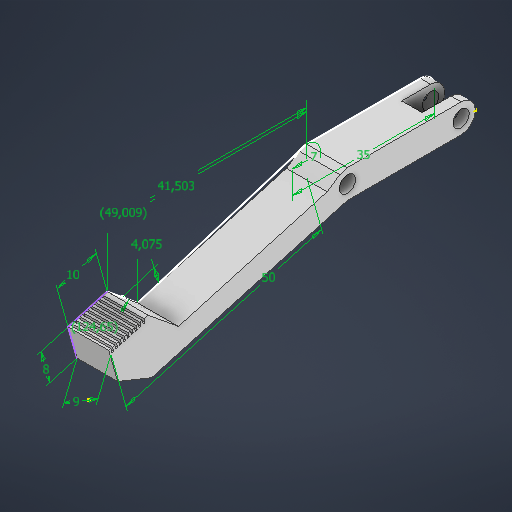
# Autodesk Inventor part: 22.10.2025-20
Saved by Autodesk Inventor 2026.1 (Build 301233020, 233B)
## iProperties
Created: 2026-01-25
Part Number: 22.10.2025-20
Material: Ogólny
Document SubType Name: Modeling
Designer: Nitro
Density: 1 g/cm^3
Appearance: Domyślna
Description: Element chwytający
Author: Nitro
Autodesk Inventor part; units mm, degrees
ref_plane "YZ Plane" through (0, 0, 0) normal (1, 0, 0) x (0, 1, 0)
ref_plane "XZ Plane" through (0, 0, 0) normal (0, 1, 0) x (-1, 0, 0)
ref_plane "XY Plane" through (0, 0, 0) normal (0, 0, 1) x (1, 0, 0)
sketch "Szkic1" plane through (0, 0, 0) normal (1, 0, 0) x (0, 1, 0)
  line L0 (0, 0) -> (0, 35) construction
  line L1 (3.5, 3.5) -> (3.5, 31.5)
  line L2 (-3.5, 31.5) -> (-3.5, 3.5)
  arc A0 (-3.5, 3.5) -> (3.5, 3.5) centre (0, 3.5) ccw
  arc A1 (3.5, 31.5) -> (-3.5, 31.5) centre (0, 31.5) ccw
  line L3 (-3.5, 31.5) -> (-17.1777, 79.5928)
  line L4 (-17.1777, 79.5928) -> (-13.8115, 87.9396)
  line L5 (-13.8115, 87.9396) -> (-6.1166, 90.128)
  line L6 (-6.1166, 90.128) -> (-3.3811, 80.5095)
  point P0 (0, 17.5)
  dimension "d0" = 35
  dimension "d1" = 7
  dimension "d2" = 50
  dimension "d3" = 9
  dimension "d4" = 8
  dimension "d5" = 10
  constraints: 16 end point, 6 point on circle, 4 tangent, 2 centre point, 2 parallel, 2 point on line, 1 midpoint, 1 perpendicular, 1 vertical
  measures "d0" distance of L0.start L0.end
  measures "d1" diameter of A1
  measures "d2" distance of L2.start L3.end
  measures "d3" distance of L3.end L4.end
  measures "d4" distance of L4.end L5.end
  measures "d5" distance of L5.end L6.end
sketch "Szkic2" plane through (0, 0, 0) normal (1, 0, 0) x (0, 1, 0)
  line L0 (-6.1166, 90.128) -> (-3.3811, 80.5095) projected
  line L1 (-13.8115, 87.9396) -> (-6.1166, 90.128) projected
  line L2 (-17.1777, 79.5928) -> (-13.8115, 87.9396) projected
  line L3 (-3.5, 31.5) -> (-17.1777, 79.5928) projected
  arc A0 (3.5, 31.5) -> (-3.5, 31.5) centre (0, 31.5) ccw projected
  line L4 (-3.5, 31.5) -> (-3.5, 3.5) projected
  line L5 (-3.3811, 80.5095) -> (-9.5635, 73.0033)
  line L6 (-9.5635, 73.0033) -> (3.5, 31.5)
  point P0 (0, 0)
  point P1 (-6.4723, 76.7564)
  dimension "d6" = 41.5033
  dimension "d7" = 4.0754
  dimension "d8" = 124.648
  dimension "d9" = 49.0095
  constraints: 4 end point, 1 midpoint
  measures "d6" vertical distance of L5.end L6.end
  measures "d7" distance from line of L6 point (-6.472, 76.756)
  measures "d8" angle of L5 L0
  measures "d9" vertical distance of A0.centre L0.end
sketch "Szkic3" plane through (0, 0, 0) normal (1, 0, 0) x (0, 1, 0)
  arc A0 (-3.5, 3.5) -> (3.5, 3.5) centre (0, 3.5) ccw projected
  line L0 (3.5, 3.5) -> (3.5, 31.5) projected
  line L1 (-3.5, 31.5) -> (-3.5, 3.5) projected
  arc A1 (3.5, 31.5) -> (-3.5, 31.5) centre (0, 31.5) ccw projected
  line L2 (-3.5, 31.5) -> (-17.1777, 79.5928) projected
  line L3 (-9.5635, 73.0033) -> (3.5, 31.5) projected
  line L4 (-17.1777, 79.5928) -> (-13.8115, 87.9396) projected
  line L5 (-13.8115, 87.9396) -> (-6.1166, 90.128) projected
  line L6 (-6.1166, 90.128) -> (-3.3811, 80.5095) projected
  line L7 (-3.3811, 80.5095) -> (-9.5635, 73.0033) projected
  point P0 (0, 0)
  point P1 (0, 17.5)
extrude "Wyciągnięcie proste1" add sketch "Szkic3" along normal blind 10 contours L1 A1 L3 L0 A0 | L2 L4 L5 L6 L7 L3 A1
sketch "Szkic4" plane through (10, 0, 0) normal (1, 0, 0) x (0, 0, -1)
  point P0 (0, 0)
sketch "Szkic5" plane through (10, 0, 0) normal (1, 0, 0) x (0, 0, -1)
  arc A0 (-3.5, -3.5) -> (-3.5, 3.5) centre (-3.5, 0) ccw projected
  circle A1 centre (-3.5, 0) radius 2.25
  circle A2 centre (-31.4611, 0) radius 2.25
  line L0 (-31.5, 3.5) -> (-73.0033, -9.5635) projected
  point P0 (0, 0)
  dimension "d12" = 4.5
  dimension "d13" = 4.5
  dimension "d14" = 3.3502
  dimension "d15" = 27.9611
  constraints: 2 centre point, 1 coincident
  measures "d12" diameter of A1
  measures "d13" diameter of A2
  measures "d14" distance from line of L0 A2.centre
  measures "d15" distance of A1.centre A2.centre
extrude "Wyciągnięcie proste2" cut sketch "Szkic5" against normal blind 10
sketch "Szkic6" plane through (10, 0, 0) normal (1, 0, 0) x (0, 0, -1)
  line L0 (-31.5, 3.5) -> (-73.0033, -9.5635) projected
  line L1 (-73.0033, -9.5635) -> (-36.4451, 0.8337)
  line L2 (-79.5928, -17.1777) -> (-31.5, -3.5) projected
  line L3 (-36.4451, 0.8337) -> (-33.3272, 2.9249)
  point P0 (0, 0)
  dimension "d18" = 3.1179
  dimension "d19" = 2.0912
  constraints: 4 end point, 1 parallel, 1 point on line
  measures "d18" horizontal distance of L1.end L3.end
  measures "d19" vertical distance of L1.end L3.end
extrude "Wyciągnięcie proste3" cut sketch "Szkic6" against normal blind 10
sketch "Szkic7" plane through (0, -13.8115, 87.9396) normal (0, -0.2736, 0.9619) x (1, 0, 0)
  point P0 (0, -10.7716)
sketch "Szkic8" plane through (0, -6.1166, 90.128) normal (0, 0.9619, 0.2736) x (1, 0, 0)
  line L0 (0, 10) -> (0, 0) projected
  line L1 (10, 10) -> (10, 0) projected
  line L2 (0, 0.5221) -> (10, 0.5221)
  line L3 (10, 0.5221) -> (10, 0.9595)
  line L4 (10, 0.9595) -> (0, 0.9595)
  line L5 (0, 0.9595) -> (0, 0.5221)
  line L6 (10, 1.9595) -> (0, 1.9595)
  line L7 (0, 1.5221) -> (10, 1.5221)
  line L8 (10, 2.9595) -> (0, 2.9595)
  line L9 (0, 2.5221) -> (10, 2.5221)
  line L10 (10, 3.9595) -> (0, 3.9595)
  line L11 (0, 3.5221) -> (10, 3.5221)
  line L12 (10, 4.9595) -> (0, 4.9595)
  line L13 (0, 4.5221) -> (10, 4.5221)
  line L14 (10, 5.9595) -> (0, 5.9595)
  line L15 (0, 5.5221) -> (10, 5.5221)
  line L16 (10, 6.9595) -> (0, 6.9595)
  line L17 (0, 6.5221) -> (10, 6.5221)
  line L18 (10, 7.9595) -> (0, 7.9595)
  line L19 (0, 7.5221) -> (10, 7.5221)
  line L20 (10, 8.9595) -> (0, 8.9595)
  line L21 (0, 8.5221) -> (10, 8.5221)
  line L22 (0, 0) -> (10, 0) projected
  point P0 (0, 88.3635)
  point P1 (0, 8.5221)
  point P2 (10, 8.5221)
  point P3 (10, 8.9595)
  point P4 (0, 8.9595)
  point P5 (0, 7.5221)
  point P6 (10, 7.5221)
  point P7 (10, 7.9595)
  point P8 (0, 7.9595)
  point P9 (0, 6.5221)
  point P10 (10, 6.5221)
  point P11 (10, 6.9595)
  point P12 (0, 6.9595)
  point P13 (0, 5.5221)
  point P14 (10, 5.5221)
  point P15 (10, 5.9595)
  point P16 (0, 5.9595)
  point P17 (0, 4.5221)
  point P18 (10, 4.5221)
  point P19 (10, 4.9595)
  point P20 (0, 4.9595)
  point P21 (0, 3.5221)
  point P22 (10, 3.5221)
  point P23 (10, 3.9595)
  point P24 (0, 3.9595)
  point P25 (0, 2.5221)
  point P26 (10, 2.5221)
  point P27 (10, 2.9595)
  point P28 (0, 2.9595)
  point P29 (0, 1.5221)
  point P30 (10, 1.5221)
  point P31 (10, 1.9595)
  point P32 (0, 1.9595)
  point P33 (0, 0.9595)
  point P34 (10, 0.5221)
  dimension "d27" = 1
  dimension "d29" = 0.4374
  dimension "d30" = 0.5221
  constraints: 40 end point, 32 vertical alignment, 18 parallel, 1 horizontal, 1 perpendicular, 4 other
  measures "d27" distance of L3.end L6.start
  measures "d29" distance between parallel lines of L4 L2
  measures "d30" distance between parallel lines of L22 L2
extrude "Wyciągnięcie proste4" cut sketch "Szkic8" against normal blind 1 contours L20 L1 L21 L0 | L18 L1 L19 L0 | L16 L1 L17 L0 | L14 L1 L15 L0 | L12 L1 L13 L0 | L10 L1 L11 L0 | L8 L1 L9 L0 | L6 L1 L7 L0 | L4 L1 L2 L0
sketch "Szkic9" plane through (10, 0, 0) normal (1, 0, 0) x (0, 0, -1)
  circle A0 centre (-3.5, 0) radius 2.25 projected
  circle A1 centre (-31.4611, 0) radius 2.25 projected
  line L0 (-87.2814, -5.307) -> (-87.0078, -6.2689) projected
  line L1 (-87.0078, -6.2689) -> (-87.4286, -6.3885) projected
  line L2 (-87.4286, -6.3885) -> (-87.7021, -5.4267) projected
  line L3 (-87.7021, -5.4267) -> (-88.2432, -5.5806) projected
  line L4 (-88.2432, -5.5806) -> (-87.9697, -6.5424) projected
  line L5 (-87.9697, -6.5424) -> (-88.3904, -6.6621) projected
  line L6 (-88.3904, -6.6621) -> (-88.664, -5.7002) projected
  line L7 (-88.664, -5.7002) -> (-89.2051, -5.8541) projected
  line L8 (-89.2051, -5.8541) -> (-88.9315, -6.816) projected
  line L9 (-88.9315, -6.816) -> (-89.3523, -6.9356) projected
  line L10 (-89.3523, -6.9356) -> (-89.6258, -5.9738) projected
  line L11 (-89.6258, -5.9738) -> (-90.128, -6.1166) projected
  line L12 (-90.128, -6.1166) -> (-87.9396, -13.8115) projected
  line L13 (-87.9396, -13.8115) -> (-79.5928, -17.1777) projected
  line L14 (-79.5928, -17.1777) -> (-31.5, -3.5) projected
  line L15 (-31.5, -3.5) -> (-3.5, -3.5) projected
  arc A2 (-3.5, -3.5) -> (-3.5, 3.5) centre (-3.5, 0) ccw projected
  line L16 (-3.5, 3.5) -> (-31.5, 3.5) projected
  line L17 (-31.5, 3.5) -> (-33.3272, 2.9249) projected
  line L18 (-33.3272, 2.9249) -> (-36.4451, 0.8337) projected
  line L19 (-36.4451, 0.8337) -> (-73.0033, -9.5635) projected
  line L20 (-73.0033, -9.5635) -> (-80.5095, -3.3811) projected
  line L21 (-80.5095, -3.3811) -> (-81.5102, -3.6657) projected
  line L22 (-81.5102, -3.6657) -> (-81.2367, -4.6275) projected
  line L23 (-81.2367, -4.6275) -> (-81.6574, -4.7472) projected
  line L24 (-81.6574, -4.7472) -> (-81.931, -3.7853) projected
  line L25 (-81.931, -3.7853) -> (-82.4721, -3.9392) projected
  line L26 (-82.4721, -3.9392) -> (-82.1985, -4.9011) projected
  line L27 (-82.1985, -4.9011) -> (-82.6193, -5.0208) projected
  line L28 (-82.6193, -5.0208) -> (-82.8928, -4.0589) projected
  line L29 (-82.8928, -4.0589) -> (-83.434, -4.2128) projected
  line L30 (-83.434, -4.2128) -> (-83.1604, -5.1747) projected
  line L31 (-83.1604, -5.1747) -> (-83.5811, -5.2943) projected
  line L32 (-83.5811, -5.2943) -> (-83.8547, -4.3325) projected
  line L33 (-83.8547, -4.3325) -> (-84.3958, -4.4863) projected
  line L34 (-84.3958, -4.4863) -> (-84.1223, -5.4482) projected
  line L35 (-84.1223, -5.4482) -> (-84.543, -5.5679) projected
  line L36 (-84.543, -5.5679) -> (-84.8165, -4.606) projected
  line L37 (-84.8165, -4.606) -> (-85.3577, -4.7599) projected
  line L38 (-85.3577, -4.7599) -> (-85.0841, -5.7218) projected
  line L39 (-85.0841, -5.7218) -> (-85.5048, -5.8414) projected
  line L40 (-85.5048, -5.8414) -> (-85.7784, -4.8796) projected
  line L41 (-85.7784, -4.8796) -> (-86.3195, -5.0335) projected
  line L42 (-86.3195, -5.0335) -> (-86.046, -5.9953) projected
  line L43 (-86.046, -5.9953) -> (-86.4667, -6.115) projected
  line L44 (-86.4667, -6.115) -> (-86.7403, -5.1531) projected
  line L45 (-86.7403, -5.1531) -> (-87.2814, -5.307) projected
  circle A3 centre (-3.5, 0) radius 2
  circle A4 centre (-31.4611, 0) radius 2
  point P0 (0, 0)
  dimension "d33" = 4
  dimension "d34" = 4
  constraints: 2 centre point, 2 coincident
  measures "d33" diameter of A3
  measures "d34" diameter of A4
extrude "Wyciągnięcie proste5" add sketch "Szkic9" against normal blind 10 contours A0 | A1
sketch "Szkic10" plane through (10, 0, 0) normal (1, 0, 0) x (0, 0, -1)
  circle A0 centre (-4.5187, 0) radius 7
  point P0 (0, 0)
  dimension "d37" = 14
  constraints: 1 centre point
  measures "d37" diameter of A0
extrude "Wyciągnięcie proste6" cut sketch "Szkic10" against normal blind 7.5
sketch "Szkic11" plane through (10, 0, 0) normal (1, 0, 0) x (0, 0, -1)
  arc A0 (-10.5809, 3.5) -> (-10.5809, -3.5) centre (-4.5187, 0) ccw projected
  line L0 (-3.5, -3.5) -> (-10.5809, -3.5) projected
  line L1 (-10.5809, -3.5) -> (-3.5, -3.5)
  line L2 (-3.5, 3.5) -> (-31.5, 3.5) projected
  line L3 (-10.5809, 3.5) -> (-3.5, 3.5)
  arc A1 (-3.5, -3.5) -> (-3.5, 3.5) centre (-3.5, 0) ccw projected
  arc A2 (-3.5, -3.5) -> (-3.5, 3.5) centre (-3.5, 0) ccw
  circle A3 centre (-3.5, 0) radius 2
  point P0 (0, 0)
  constraints: 4 end point, 2 centre point, 2 point on circle, 1 coincident, 1 collinear, 1 horizontal, 1 tangent
extrude "Wyciągnięcie proste7" add sketch "Szkic11" against normal blind 2.5
